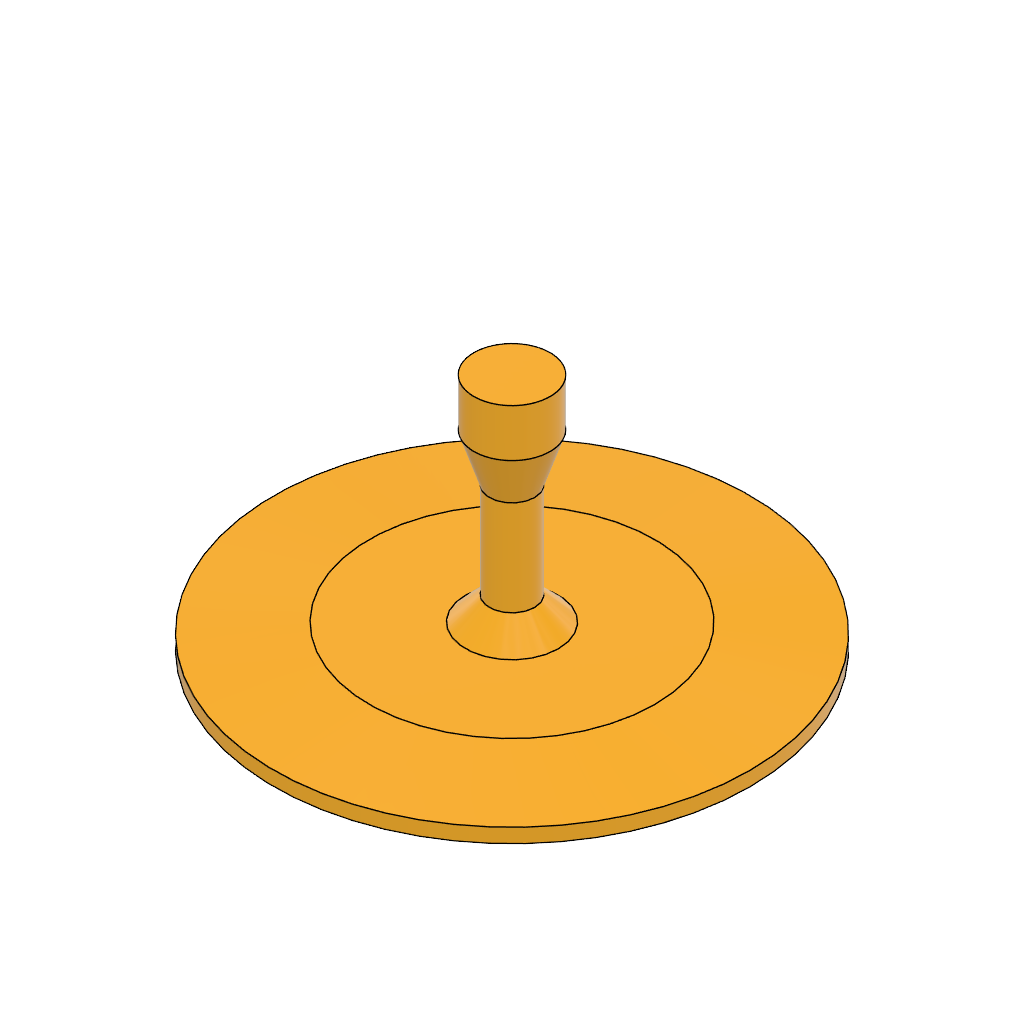
ProbingTipFlat (Autodesk Fusion 360 design; units mm, degrees)
Autodesk Fusion 360 part; units mm, degrees
cylinder "CylinderPrimitive1" add diameter 8 height 5 placed x (1, 0, 0) y (0, 0, -1) z (0, 1, 0) at (0, 0, 0) makes body 1
ref_plane "WorkPlane1" through (0, -5, 0) normal (0, -1, 0) x (-1, 0, 0)
cylinder "CylinderPrimitive2" add diameter 4.75 height 2.5 placed x (1, 0, 0) y (0, 0, 1) z (0, -1, 0) at (0, -5, 0) separate body makes body 2
loft "Loft1" add section 1 face at (0.0821, -5, 0.5322) section 2 face at (-1.2456, 0, -0.0132) on bodies 1 2 bodies 1 2
extrude "Extrude1" add 1 faces at (-0.3221, -7.5, 0.2988) along direction (0, -1, 0) blind 10 on bodies 1 bodies 1
cylinder "CylinderPrimitive4" add diameter 50 height 2.5 placed x (1, 0, 0) y (0, 0, 1) z (0, -1, 0) at (0, -17.5, 0) bodies 1
chamfer "Chamfer2" distance 10 distance2 1 1 edges at (-23.3082, -17.5, 9.0404) measured on face at (17.3564, -17.5, -1.36) tangent chain off on bodies 1
chamfer "Chamfer3" distance 2.5 angle 45 1 edges at (-2.2143, -17.5, -0.8588) tangent chain off on bodies 1
